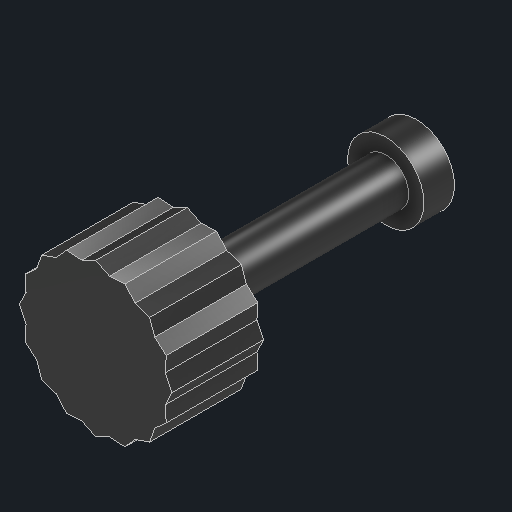
# Autodesk Inventor part: c8n_ring_clamp_knob
Saved by Autodesk Inventor 2027.1 (Build 311270010, 270A)
## iProperties
Created: 2026-11-04
Part Number: c8n_ring_clamp_knob
Material: Generic
Description: Tube ring clamp thumbscrew (x2)
Document SubType Name: Modeling
Designer: Claude (from photos)
Density: 1 g/cm^3
Appearance: Glossy - Black
Author: alexg
Autodesk Inventor part; units mm, degrees
ref_plane "Work Plane1" through (0, 0, -13) normal (0, 0, 1) x (1, 0, 0)
sketch "Clamp screw sketch" plane through (0, 0, -13) normal (0, 0, 1) x (1, 0, 0)
  circle A0 centre (0, 140) radius 3
  constraints: 1 centre point
extrude "Clamp screw" add sketch "Clamp screw sketch" along normal blind 26
ref_plane "Work Plane2" through (0, 0, -13) normal (0, 0, 1) x (1, 0, 0)
sketch "Screw head sketch" plane through (0, 0, -13) normal (0, 0, 1) x (1, 0, 0)
  circle A0 centre (0, 140) radius 5
  constraints: 1 centre point
extrude "Screw head" add sketch "Screw head sketch" against normal blind 4
ref_plane "Work Plane3" through (0, 0, 13) normal (0, 0, 1) x (1, 0, 0)
sketch "Thumb knob sketch" plane through (0, 0, 13) normal (0, 0, 1) x (1, 0, 0)
  line L0 (10, 140) -> (9.1213, 141.8143)
  line L1 (9.1213, 141.8143) -> (9.2388, 143.8268)
  line L2 (9.2388, 143.8268) -> (7.7327, 145.1668)
  line L3 (7.7327, 145.1668) -> (7.0711, 147.0711)
  line L4 (7.0711, 147.0711) -> (5.1668, 147.7327)
  line L5 (5.1668, 147.7327) -> (3.8268, 149.2388)
  line L6 (3.8268, 149.2388) -> (1.8143, 149.1213)
  line L7 (1.8143, 149.1213) -> (0, 150)
  line L8 (0, 150) -> (-1.8143, 149.1213)
  line L9 (-1.8143, 149.1213) -> (-3.8268, 149.2388)
  line L10 (-3.8268, 149.2388) -> (-5.1668, 147.7327)
  line L11 (-5.1668, 147.7327) -> (-7.0711, 147.0711)
  line L12 (-7.0711, 147.0711) -> (-7.7327, 145.1668)
  line L13 (-7.7327, 145.1668) -> (-9.2388, 143.8268)
  line L14 (-9.2388, 143.8268) -> (-9.1213, 141.8143)
  line L15 (-9.1213, 141.8143) -> (-10, 140)
  line L16 (-10, 140) -> (-9.1213, 138.1857)
  line L17 (-9.1213, 138.1857) -> (-9.2388, 136.1732)
  line L18 (-9.2388, 136.1732) -> (-7.7327, 134.8332)
  line L19 (-7.7327, 134.8332) -> (-7.0711, 132.9289)
  line L20 (-7.0711, 132.9289) -> (-5.1668, 132.2673)
  line L21 (-5.1668, 132.2673) -> (-3.8268, 130.7612)
  line L22 (-3.8268, 130.7612) -> (-1.8143, 130.8787)
  line L23 (-1.8143, 130.8787) -> (0, 130)
  line L24 (0, 130) -> (1.8143, 130.8787)
  line L25 (1.8143, 130.8787) -> (3.8268, 130.7612)
  line L26 (3.8268, 130.7612) -> (5.1668, 132.2673)
  line L27 (5.1668, 132.2673) -> (7.0711, 132.9289)
  line L28 (7.0711, 132.9289) -> (7.7327, 134.8332)
  line L29 (7.7327, 134.8332) -> (9.2388, 136.1732)
  line L30 (9.2388, 136.1732) -> (9.1213, 138.1857)
  line L31 (9.1213, 138.1857) -> (10, 140)
  constraints: 64 end point
extrude "Thumb knob" add sketch "Thumb knob sketch" along normal blind 12
body "Solid1"
